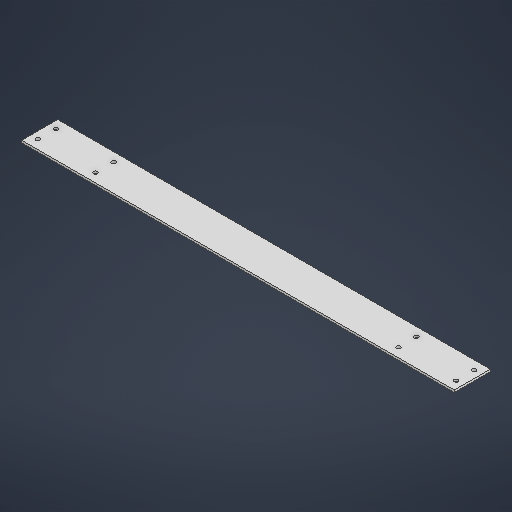
# Autodesk Inventor part: Horizontal_beam
Saved by Autodesk Inventor 2026.2 (Build 302298010, 298A)
## iProperties
Created: 2026-07-08
Part Number: Horizontal_beam
Material: Generic
Document SubType Name: Sheet Metal
Designer: User
Density: 1 g/cm^3
Sheet Metal Rule: Default
Appearance: Default
Author: User
Autodesk Inventor part; units mm, degrees
ref_plane "YZ Plane" through (0, 0, 0) normal (1, 0, 0) x (0, 1, 0)
ref_plane "XZ Plane" through (0, 0, 0) normal (0, 1, 0) x (-1, 0, 0)
ref_plane "XY Plane" through (0, 0, 0) normal (0, 0, 1) x (1, 0, 0)
sketch "Sketch1" plane through (0, 0, 0) normal (0, 1, 0) x (-1, 0, 0)
  line L0 (0, 0) -> (600, 0)
  line L1 (600, 0) -> (600, -50)
  line L2 (600, -50) -> (0, -50)
  line L3 (0, -50) -> (0, 0)
  dimension "d0" = 600
  dimension "d1" = 50
  measures "d0" distance of L1.end L2.end
  measures "d1" distance of L0.end L1.end
extrude "Plate1" add sketch "Sketch1" along normal blind 3.048
sketch "Sketch2" plane through (0, 3.048, 0) normal (0, 1, 0) x (1, 0, 0)
  line L0 (0, 0) -> (0, 50) projected
  line L1 (0, 0) -> (0, 25)
  line L2 (-600, 50) -> (-600, 0) projected
  point P0 (-10, 12.5)
  point P1 (-10, 37.5)
  point P2 (-90, 37.5)
  point P3 (-90, 12.5)
  point P4 (-510, 12.5)
  point P5 (-510, 37.5)
  point P6 (-590, 37.5)
  point P7 (-590, 12.5)
  constraints: 2 end point, 1 midpoint
hole "Hole1" at (-10, 3.048, -12.5) at (-10, 3.048, -37.5) at (-90, 3.048, -37.5) at (-90, 3.048, -12.5) at (-510, 3.048, -37.5) at (-510, 3.048, -12.5) at (-590, 3.048, -37.5) at (-590, 3.048, -12.5) direction (0, -1, 0) diameter 5.5 end through all
equation "\"d2\" = Thickness"
equation "\"BendRadius\" = Thickness"
equation "\"BendReliefWidth\" = Thickness"
equation "\"BendReliefDepth\" = 0.5 * Thickness"
equation "\"CornerReliefSize\" = 4 * Thickness"
equation "\"MinimumRemnant\" = 2 * Thickness"
equation "\"TransitionRadius\" = BendRadius"
equation "\"JacobiRadiusSize\" = BendRadius"
equation "\"GapSize\" = Thickness"
equation "\"Thickness\" = 3.048"
body "Solid1"
